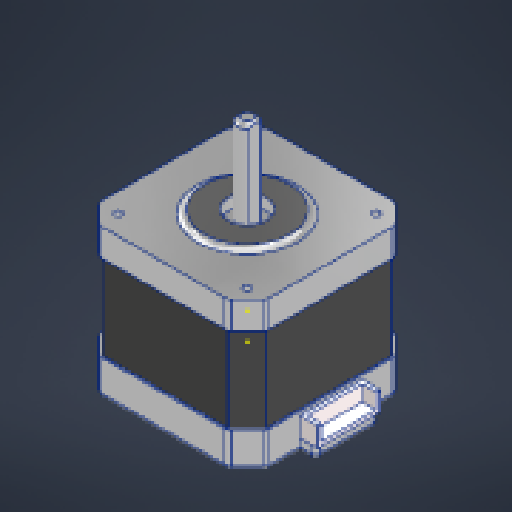
# Autodesk Inventor part: NEMA17
Saved by Autodesk Inventor 2026.2 (Build 302298010, 298A)
## iProperties
Created: 2025-09-08
Part Number: NEMA17
Material: 강철, 아연도금
Document SubType Name: Modeling
Designer: work
Density: 7.85 g/cm^3
Appearance: 알루미늄 - 평지
Author: work
Autodesk Inventor part; units mm, degrees
ref_plane "YZ Plane" through (0, 0, 0) normal (1, 0, 0) x (0, 1, 0)
ref_plane "XZ Plane" through (0, 0, 0) normal (0, 1, 0) x (-1, 0, 0)
ref_plane "XY Plane" through (0, 0, 0) normal (0, 0, 1) x (1, 0, 0)
sketch "스케치1" plane through (0, 0, 0) normal (0, 1, 0) x (-1, 0, 0)
  line L0 (0, 0) -> (43, 0)
  line L1 (43, 0) -> (43, -43)
  line L2 (43, -43) -> (0, -43)
  line L3 (0, -43) -> (0, 0)
  dimension "d0" = 43
  dimension "d1" = 43
  constraints: 8 end point, 2 parallel, 1 horizontal, 1 perpendicular
  measures "d0" distance of L1.end L2.end
  measures "d1" distance of L0.end L1.end
extrude "돌출1" add sketch "스케치1" along normal blind 9
chamfer "모따기1" distance 5 angle 45 4 edges at (0, 4.5, 0) (0, 4.5, -43) (-43, 4.5, 0) (-43, 4.5, -43)
sketch "스케치2" plane through (0, 9, 0) normal (0, 1, 0) x (1, 0, 0)
  line L0 (-6.8284, 0) -> (-36.1716, 0)
  line L1 (-43, 6.8284) -> (-43, 36.1716)
  line L2 (-36.1716, 43) -> (-6.8284, 43)
  line L3 (0, 36.1716) -> (0, 6.8284)
  line L4 (-37.5858, 0.5858) -> (-42.4142, 5.4142)
  line L5 (-42.4142, 37.5858) -> (-37.5858, 42.4142)
  line L6 (-5.4142, 42.4142) -> (-0.5858, 37.5858)
  line L7 (-5.4142, 0.5858) -> (-0.5858, 5.4142)
  arc A0 (-6.8284, 0) -> (-5.4142, 0.5858) centre (-6.8284, 2) ccw
  arc A1 (-0.5858, 5.4142) -> (0, 6.8284) centre (-2, 6.8284) ccw
  arc A2 (0, 36.1716) -> (-0.5858, 37.5858) centre (-2, 36.1716) ccw
  arc A3 (-5.4142, 42.4142) -> (-6.8284, 43) centre (-6.8284, 41) ccw
  arc A4 (-36.1716, 43) -> (-37.5858, 42.4142) centre (-36.1716, 41) ccw
  arc A5 (-42.4142, 37.5858) -> (-43, 36.1716) centre (-41, 36.1716) ccw
  arc A6 (-43, 6.8284) -> (-42.4142, 5.4142) centre (-41, 6.8284) ccw
  arc A7 (-37.5858, 0.5858) -> (-36.1716, 0) centre (-36.1716, 2) ccw
  point P0 (0, 0)
  point P1 (-43, 43)
  point P2 (-43, 0)
  point P3 (0, 43)
  point P4 (-37, 0)
  point P5 (-43, 6)
  point P6 (-43, 37)
  point P7 (-37, 43)
  point P8 (-6, 43)
  point P9 (0, 37)
  point P10 (-6, 0)
  point P11 (0, 6)
  dimension "d7" = 43
  dimension "d8" = 43
  dimension "d9" = 6
  dimension "d10" = 6
  dimension "d11" = 6
  dimension "d12" = 6
  dimension "d13" = 6
  dimension "d14" = 6
  dimension "d15" = 6
  dimension "d16" = 6
  dimension "d17" = 2
  constraints: 24 point on line, 16 end point, 16 point on circle, 16 tangent, 8 centre point, 7 equal radius, 2 parallel, 1 horizontal, 1 perpendicular
  measures "d7" distance of point (-43, 43) point (0, 43)
  measures "d8" distance of point (-43, 0) point (-43, 43)
  measures "d9" distance of point (-37, 0) point (-43, 0)
  measures "d10" distance of point (-43, 6) point (-43, 0)
  measures "d11" distance of point (-43, 37) point (-43, 43)
  measures "d12" distance of point (-37, 43) point (-43, 43)
  measures "d13" distance of point (-6, 43) point (0, 43)
  measures "d14" distance of point (0, 37) point (0, 43)
  measures "d15" distance of point (-6, 0) point (0, 0)
  measures "d16" distance of point (0, 6) point (0, 0)
  measures "d17" radius of A0
extrude "돌출2" add sketch "스케치2" along normal blind 22
sketch "스케치3" plane through (0, 31, 0) normal (0, 1, 0) x (1, 0, 0)
  point P0 (0, 0)
sketch "스케치4" plane through (0, 31, 0) normal (0, 1, 0) x (1, 0, 0)
  line L0 (0, 0) -> (-43, 0)
  line L1 (-43, 0) -> (-43, 43)
  line L2 (-43, 43) -> (0, 43)
  line L3 (0, 43) -> (0, 0)
  dimension "d20" = 43
  dimension "d21" = 43
  constraints: 8 end point, 2 parallel, 1 horizontal, 1 perpendicular
  measures "d20" distance of L1.end L2.end
  measures "d21" distance of L0.end L1.end
extrude "돌출3" add sketch "스케치4" along normal blind 7
chamfer "모따기2" distance 5 angle 45 4 edges at (0, 34.5, 0) (0, 34.5, -43) (-43, 34.5, 0) (-43, 34.5, -43)
sketch "스케치5" plane through (0, 38, 0) normal (0, 1, 0) x (1, 0, 0)
  circle A0 centre (-21.5, 21.5) radius 2.5
  line L0 (-5, 43) -> (-38, 43) projected
  line L1 (0, 5) -> (0, 38) projected
  line L2 (-19.5, 23) -> (-19.5, 20)
  point P0 (0, 0)
  dimension "d27" = 5
  dimension "d28" = 21.5
  dimension "d29" = 21.5
  dimension "d30" = 4.5
  constraints: 2 end point, 2 point on circle, 1 centre point, 1 vertical
  measures "d27" diameter of A0
  measures "d28" distance from line of L0 A0.centre
  measures "d29" distance from line of L1 A0.centre
extrude "돌출4" add sketch "스케치5" along normal blind 22.2 contours L2 A0 picked at (-21.2595, 20.7991)
sketch "스케치6" plane through (0, 0, 0) normal (0, -1, 0) x (1, 0, 0)
  arc A0 (-19.5, -20) -> (-19.5, -23) centre (-21.5, -21.5) ccw projected
  circle A1 centre (-21.5, -21.5) radius 3.5
  point P0 (0, 0)
  dimension "d33" = 7
  constraints: 1 centre point, 1 coincident
  measures "d33" diameter of A1
extrude "돌출5" cut sketch "스케치6" against normal blind 3.5
sketch "스케치7" plane through (0, 0, 0) normal (0, -1, 0) x (1, 0, 0)
  line L0 (0, -5) -> (0, -38) projected
  line L1 (0, -13.5) -> (4, -13.5)
  line L2 (4, -13.5) -> (4, -29.5)
  line L3 (4, -29.5) -> (0, -29.5)
  line L4 (0, -29.5) -> (0, -13.5)
  point P0 (0, 0)
  point P1 (0, -21.5)
  point P2 (0, -29.5)
  dimension "d36" = 4
  dimension "d37" = 16
  constraints: 8 end point, 2 midpoint, 2 parallel, 1 horizontal, 1 perpendicular, 1 point on line
  measures "d36" distance of L2.end L3.end
  measures "d37" distance of L1.end L2.end
extrude "돌출6" add sketch "스케치7" against normal blind 3
sketch "스케치8" plane through (0, 3, 0) normal (0, 1, 0) x (1, 0, 0)
  line L0 (0, 13.5) -> (0, 29.5) projected
  line L1 (0, 13.5) -> (4.5, 13.5)
  line L2 (4.5, 13.5) -> (4.5, 29.5)
  line L3 (4.5, 29.5) -> (0, 29.5)
  line L4 (0, 29.5) -> (0, 13.5)
  point P0 (0, 0)
  dimension "d40" = 4.5
  constraints: 8 end point, 2 parallel, 1 horizontal, 1 perpendicular
  measures "d40" distance of L3.end L2.end
extrude "돌출7" add sketch "스케치8" along normal blind 5 separate body
shell "쉘1" thickness 1 removed faces 2 at (4.5, 4.6667, -18.8333) at (1.5, 8, -18.8333) bodies 2
sketch "스케치9" plane through (0, 38, 0) normal (0, 1, 0) x (1, 0, 0)
  arc A0 (-19.5, 23) -> (-19.5, 20) centre (-21.5, 21.5) ccw projected
  circle A1 centre (-21.5, 21.5) radius 11
  point P0 (0, 0)
  dimension "d44" = 22
  constraints: 1 centre point, 1 coincident
  measures "d44" diameter of A1
extrude "돌출8" add sketch "스케치9" along normal blind 1 bodies 1
sketch "스케치10" plane through (-21.5, 39, -21.5) normal (0, 1, 0) x (1, 0, 0)
  arc A0 (2, 1.5) -> (2, -1.5) centre (0, 0) ccw projected
  arc A1 (2, 1.5) -> (2, -1.5) centre (0, 0) ccw projected
  line L0 (2, -1.5) -> (2, 1.5) projected
  circle A2 centre (0, 0) radius 5
  point P0 (21.5, -21.5)
  point P1 (2, -1.5)
  point P2 (2, 1.5)
  dimension "d47" = 10
  constraints: 1 centre point, 1 coincident
  measures "d47" diameter of A2
extrude "돌출9" cut sketch "스케치10" against normal blind 3 bodies 1
sketch "스케치11" plane through (0, 38, 0) normal (0, 1, 0) x (1, 0, 0)
  point P0 (0, 0)
sketch "스케치12" plane through (-21.5, 3.5, -21.5) normal (0, -1, 0) x (1, 0, 0)
  circle A0 centre (0, 0) radius 5 projected
  circle A1 centre (0, 0) radius 2.5
  point P0 (21.5, 21.5)
  constraints: 1 centre point, 1 coincident
extrude "돌출10" add sketch "스케치12" along normal blind 1 contours A1 bodies 1
sketch "스케치13" plane through (0, 38, 0) normal (0, 1, 0) x (1, 0, 0)
  circle A0 centre (-5, 5) radius 1
  line L0 (0, 5) -> (0, 38) projected
  line L1 (-38, 0) -> (-5, 0) projected
  circle A1 centre (-21.5, 21.5) radius 11 projected
  line L2 (-43, 38) -> (-38, 43) projected
  line L3 (-43, 38) -> (-43, 5) projected
  line L4 (-38, 0) -> (-43, 5) projected
  line L5 (-38, 0) -> (-5, 0) projected
  line L6 (0, 5) -> (-5, 0) projected
  line L7 (0, 5) -> (0, 38) projected
  line L8 (-5, 43) -> (0, 38) projected
  line L9 (-5, 43) -> (-38, 43) projected
  circle A2 centre (-5, 38) radius 1
  circle A3 centre (-38, 38) radius 1
  circle A4 centre (-38, 5) radius 1
  point P0 (0, 0)
  dimension "d52" = 2
  dimension "d53" = 4
  dimension "d54" = 4
  dimension "d57" = 360
  constraints: 4 centre point, 9 other
  measures "d52" diameter of A0
  measures "d53" distance edge to line of A0 L0
  measures "d54" distance edge to line of A0 L1
extrude "돌출11" cut sketch "스케치13" against normal blind 5 contours A0 | A2 | A3 | A4 bodies 1
sketch "스케치14" plane through (0, 9, 0) normal (0, 1, 0) x (1, 0, 0)
  line L0 (-5, 43) -> (-38, 43) projected
  line L1 (-21.5, 43) -> (-21.5, 0) construction
  line L2 (-43, 38) -> (-43, 5) projected
  line L3 (-43, 21.5) -> (0, 21.5) construction
  line L4 (0, 13.5) -> (0, 29.5) projected
  line L5 (-43, 43) -> (0, 43)
  line L6 (0, 43) -> (0, 0)
  line L7 (0, 0) -> (-43, 0)
  line L8 (-43, 0) -> (-43, 43)
  circle A0 centre (-21.5, 21.5) radius 2.5 projected
  line L9 (-43, 43) -> (0, 0) construction
  line L10 (0, 43) -> (-43, 0) construction
  line L11 (-42.5, 42.5) -> (-0.5, 42.5)
  line L12 (-0.5, 42.5) -> (-0.5, 0.5)
  line L13 (-0.5, 0.5) -> (-42.5, 0.5)
  line L14 (-42.5, 0.5) -> (-42.5, 42.5)
  circle A1 centre (-21.5, 21.5) radius 3.5 projected
  line L15 (-42.5, 42.5) -> (-0.5, 0.5) construction
  line L16 (-0.5, 42.5) -> (-42.5, 0.5) construction
  dimension "d61" = 43
  dimension "d62" = 43
  dimension "d63" = 42
  dimension "d64" = 42
  constraints: 28 end point, 7 midpoint, 4 parallel, 2 horizontal, 2 perpendicular, 1 vertical
  measures "d61" distance of L6.end L7.end
  measures "d62" distance of L5.end L6.end
  measures "d63" distance of L12.end L13.end
  measures "d64" distance of L11.end L12.end
extrude "돌출12" cut sketch "스케치14" along normal up to surface (22 mm away) contours L5 L6 L4 L7 L8 L2 L0 bodies 1
fillet "모깎기1" radius 2 17 edges at (-5, 34.5, 0) (0, 34.5, -5) (0, 34.5, -38) (-5, 34.5, -43) (-32.5, 38, -21.5) (-38, 34.5, -43) (-43, 34.5, -38) (-43, 34.5, -5) (-38, 34.5, 0) (-38, 4.5, 0) (-43, 4.5, -5) (-43, 4.5, -38) (-38, 4.5, -43) (-5, 4.5, -43) (0, 4.5, -38) (0, 4.5, -5) (-5, 4.5, 0)
chamfer "모따기3" distance 1 angle 45 1 edges at (-24, 60.2, -21.5)
fillet "모깎기2" radius 1 23 edges at (-5.0631, 0, -0.1522) (-2.5, 0, -2.5) (-0.1522, 0, -5.0631) (0, 0, -9.6642) (-37.9369, 0, -0.1522) (-40.5, 0, -2.5) (-42.8478, 0, -5.0631) (-43, 0, -21.5) (-42.8478, 0, -37.9369) (-40.5, 0, -40.5) (-37.9369, 0, -42.8478) (-21.5, 0, -43) (-5.0631, 0, -42.8478) (-2.5, 0, -40.5) (-0.1522, 0, -37.9369) (0, 0, -33.3358) (-21.5, 0, 0) (-25, 0, -21.5) (4, 1.5, -13.5) (2, 0, -13.5) (4, 0, -21.5) (4, 1.5, -29.5) (2, 0, -29.5)
equation "\"d10\" = d9"
equation "\"d11\" = d9"
equation "\"d12\" = d11"
equation "\"d13\" = d9"
equation "\"d14\" = d13"
equation "\"d15\" = d9"
equation "\"d16\" = d15"
